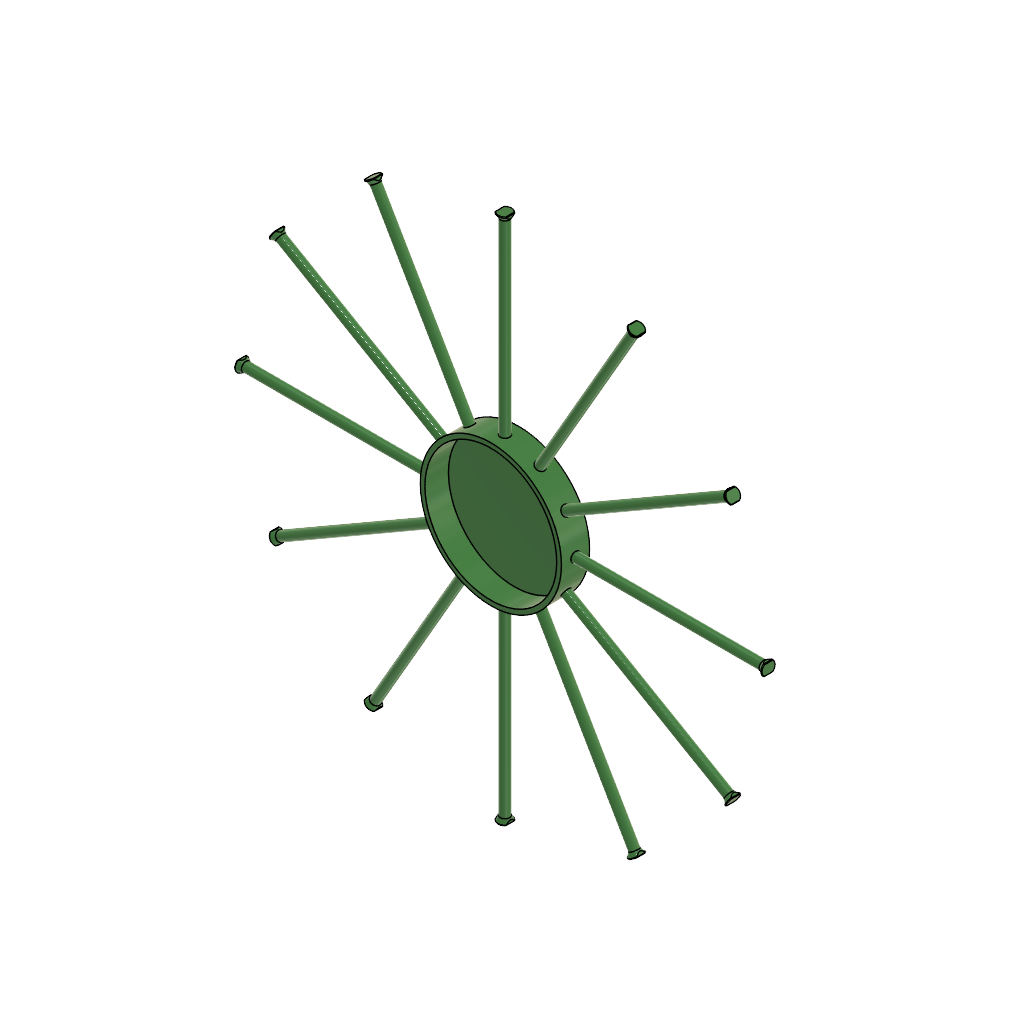
scanner_assemblage (Autodesk Fusion 360 archive; units mm, degrees)
design "patte"
part number: 2026-11-27-08-09-07-575
Autodesk Fusion 360 part; units mm, degrees
sketch "Esquisse1" plane through (0, 0, 0) normal (0, 1, 0) x (1, 0, 0)
  circle A0 centre (0, 0) radius 15
  dimension "d1" = 30
  constraint coincident A0.centre origin
  measures "d1" diameter of A0
extrude "Extrusion1" add sketch "Esquisse1" along normal mid plane 6
shell "Coque1" thickness 1 removed faces 1 at (3.8315, -3, -5.6199)
sketch "Esquisse2" plane through (0, 3, 0) normal (0, 1, 0) x (-1, 0, 0)
  circle A0 centre (0, 0) radius 15
  circle A1 centre (0, 0) radius 2.5
  circle A2 centre (0, 0) radius 3.5
  dimension "d5" = 5
  dimension "d6" = 7
  constraint coincident A0.centre A1.centre
  constraint concentric A1 A2
  measures "d5" diameter of A1
  measures "d6" diameter of A2
extrude "Extrusion2" add sketch "Esquisse2" along normal blind 3 contours A2
ref_plane "Plan de construction1" through (0, -1.1036, 15) normal (0, 0, 1) x (-1, 0, 0)
sketch "Esquisse3" plane through (0, 0, 15) normal (0, 0, 1) x (1, 0, 0)
  circle A0 centre (0, 0) radius 1
  dimension "d11" = 2
  constraint coincident A0.centre origin
  measures "d11" diameter of A0
extrude "Extrusion3" add sketch "Esquisse3" along normal blind 40
sketch "Esquisse5" plane through (0, 0, 55) normal (0, 0, 1) x (-1, 0, 0)
  circle A0 centre (0, 0) radius 1
  circle A1 centre (0, 0) radius 1
  constraint coincident A0.centre A1.centre
extrude "Extrusion4" add sketch "Esquisse5" along normal blind 1 draft 30
ref_plane "Plan de construction2" through (1.5774, 0, 56) normal (0, -1, 0) x (0, 0, 1)
sketch "Esquisse6" plane through (1.5774, 0, 56) normal (0, -1, 0) x (0, 0, 1)
  line L0 (0, 0.4) -> (-0.7, 0.4)
  line L1 (-0.7, 0.4) -> (-0.7, -0.1)
  line L2 (-0.7, -0.1) -> (0.1, -0.1)
  line L3 (0.1, -0.1) -> (0.1, 0.4)
  line L4 (0.1, 0.4) -> (0, 0.4)
  constraint horizontal L0
  constraint perpendicular L0 L1
  constraint perpendicular L1 L2
  constraint perpendicular L0 L3
  constraint perpendicular L3 L4
extrude "Extrusion5" cut sketch "Esquisse6" along normal mid plane 20
mirror "Symétrie miroir1" about plane through (0, 0, 0) normal (1, 0, 0) of "Extrusion5"
fillet "Congé1" radius 0.1 4 edges at (0, -1.5774, 56) (1.1774, 0, 56) (0, 1.5774, 56) (-1.1774, 0, 56)
pattern_circular "Réseau C1" count 12 over 360 about axis through (0, -3, 0) along (0, -1, 0) of "Extrusion3", "Extrusion4", "Extrusion5", "Symétrie miroir1", "Congé1"

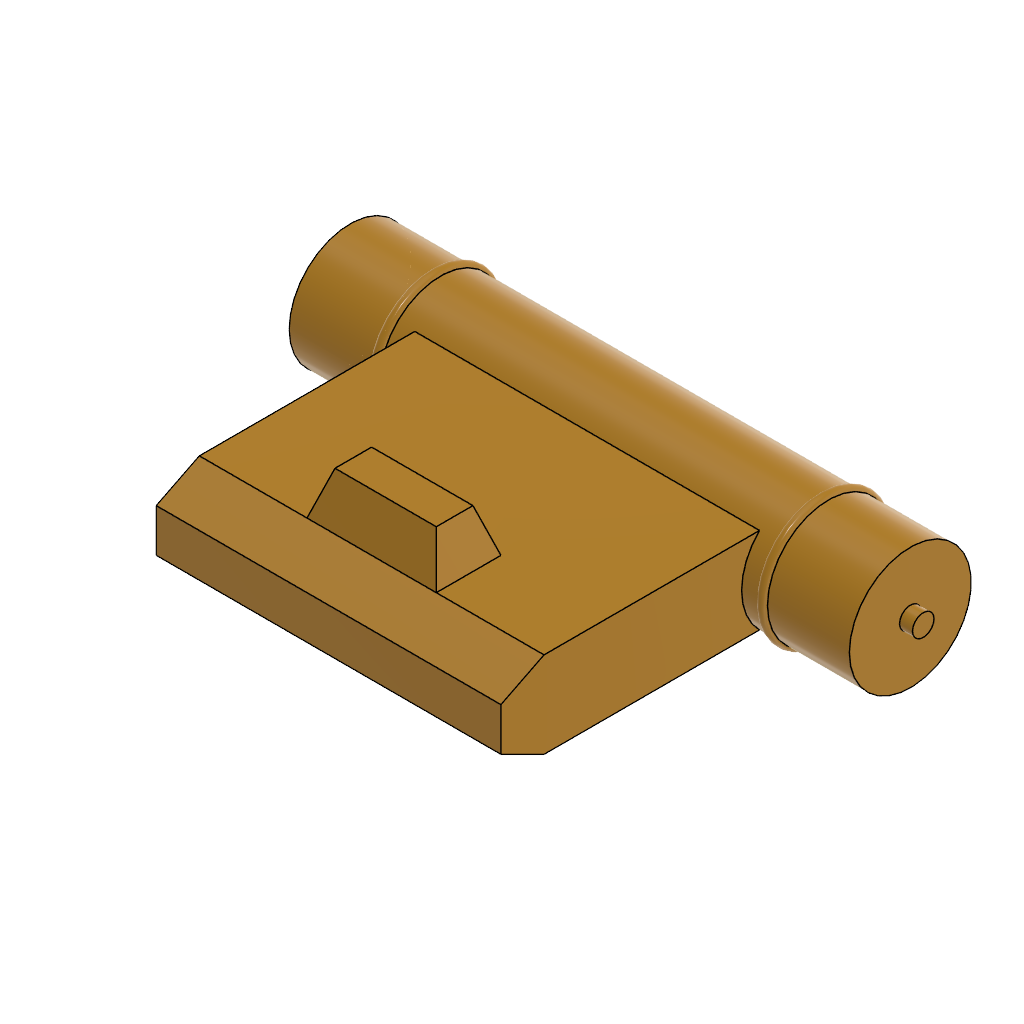
design "scanner_corps"
part number: 2026-11-27-06-16-49-714
Autodesk Fusion 360 part; units mm, degrees
sketch "Esquisse1" plane through (0, 0, 0) normal (0, 0, 1) x (1, 0, 0)
  line L0 (40, -30) -> (-40, -30)
  line L1 (-40, -30) -> (-40, 30)
  line L2 (-40, 30) -> (40, 30)
  line L3 (40, 30) -> (40, -30)
  line L4 (40, -30) -> (-40, 30) construction
  line L5 (-40, -30) -> (40, 30) construction
  dimension "d26" = 60
  constraint horizontal L0
  constraint perpendicular L0 L1
  constraint parallel L0 L2
  constraint parallel L1 L3
  constraint coincident L4 origin
  constraint coincident L5 origin
  measures "d26" distance of L0.end L1.end
extrude "Extrusion5" add sketch "Esquisse1" along normal blind 20
sketch "Esquisse7" plane through (40, 0, 0) normal (1, 0, 0) x (0, 1, 0)
  line L0 (-30, 0) -> (30, 0)
  line L1 (30, 0) -> (30, 20)
  line L2 (30, 20) -> (-30, 20)
  line L3 (-30, 20) -> (-30, 0)
  circle A0 centre (40, 10) radius 14.1421
extrude "Extrusion6" add sketch "Esquisse7" along normal blind 25 and the other way blind 105 contours L1 A0 | L1 A0
ref_plane "Plan de construction5" through (45, 40, 10) normal (1, 0, 0) x (0, 1, 0)
sketch "Esquisse8" plane through (45, 0, 0) normal (1, 0, 0) x (0, 1, 0)
  circle A0 centre (40, 10) radius 14.1421
pipe "Tuyau2" add diameter 2 path "Esquisse8" along A0
ref_plane "Plan de construction6" through (0, 0, 10) normal (1, 0, 0) x (0, 1, 0)
mirror "Symétrie miroir3" about plane through (0, 0, 10) normal (1, 0, 0) of "Tuyau2"
sketch "Esquisse9" plane through (40, 0, 0) normal (1, 0, 0) x (0, 1, 0)
  arc A0 (30, 20) -> (30, 0) centre (40, 10) ccw
  line L0 (30, 20) -> (-30, 20)
  line L1 (-30, 20) -> (-30, 0)
  line L2 (-30, 0) -> (30, 0)
  line L3 (-20, 20) -> (-30, 15)
  line L4 (-20, 0) -> (-30, 5)
  constraint coincident L0 L3.start
  constraint coincident L1 L3.end
  constraint coincident L2 L4.start
  constraint coincident L1 L4.end
extrude "Extrusion7" cut sketch "Esquisse9" against normal blind 100 contours L0 L1 L3
extrude "Extrusion8" cut sketch "Esquisse9" against normal blind 100 contours L1 L2 L4
sketch "Esquisse10" plane through (0, 0, 20) normal (0, 0, 1) x (-1, 0, 0)
  line L0 (40, 20) -> (-40, 20)
  line L1 (-40, 20) -> (-40, -30)
  line L2 (-40, -30) -> (40, -30)
  line L3 (40, -30) -> (40, 20)
  line L4 (15, 20) -> (-15, 20)
  line L5 (-15, 20) -> (-15, 5)
  line L6 (-15, 5) -> (15, 5)
  line L7 (15, 5) -> (15, 20)
  constraint horizontal L4
  constraint vertical L5
  constraint horizontal L6
  constraint vertical L7
  constraint coincident L0 L4.start
extrude "Extrusion9" add sketch "Esquisse10" along normal blind 10 draft -18 contours L0 L4 L5 L6 L7
sketch "Esquisse11" plane through (65, 0, 0) normal (1, 0, 0) x (0, 1, 0)
  circle A0 centre (40, 10) radius 14.1421
  circle A1 centre (40, 10) radius 2.5
  dimension "d52" = 5
  constraint concentric A0 A1
  measures "d52" diameter of A1
extrude "Extrusion10" add sketch "Esquisse11" along normal blind 3 contours A1
mirror "Symétrie miroir4" about plane through (0, 0, 10) normal (1, 0, 0) of "Extrusion10"
